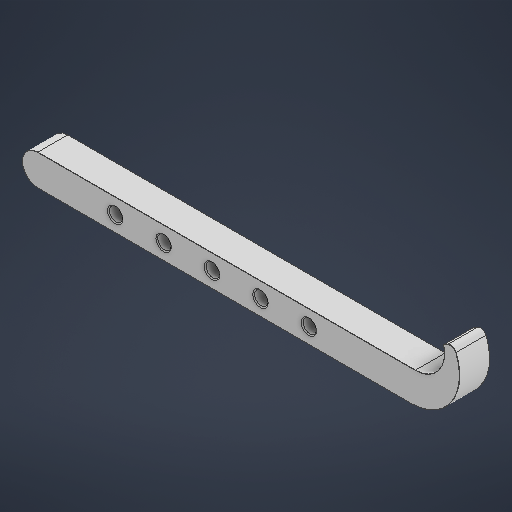
# Autodesk Inventor part: Part1
Saved by Autodesk Inventor 2025.4 (Build 294407000, 407)
## iProperties
Created: 2026-06-25
Part Number: Part1
Material: Generic
Document SubType Name: Modeling
Designer: VuQuan
Density: 1 g/cm^3
Appearance: Default
Author: VuQuan
Autodesk Inventor part; units mm, degrees
ref_plane "YZ Plane" through (0, 0, 0) normal (1, 0, 0) x (0, 1, 0)
ref_plane "XZ Plane" through (0, 0, 0) normal (0, 1, 0) x (-1, 0, 0)
ref_plane "XY Plane" through (0, 0, 0) normal (0, 0, 1) x (1, 0, 0)
sketch "Sketch1" plane through (0, 0, 0) normal (0, 0, 1) x (1, 0, 0)
  arc A0 (0, 8) -> (0, -8) centre (0, 0) ccw
  line L0 (0, 8) -> (195, 8)
  line L1 (0, -8) -> (192.8471, -8)
  arc A1 (195, 8) -> (209.5507, 26.6438) centre (195, 23) ccw
  arc A2 (192.8471, -8) -> (216, 26.4309) centre (192.8471, 17) ccw
  arc A3 (216, 26.4309) -> (211.7216, 27.8972) centre (213.2216, 25.2992) ccw
  line L2 (211.7216, 27.8972) -> (209.5507, 26.6438)
  circle A4 centre (40, 0) radius 3.5
  line L3 (0, 0) -> (40, 0) construction
  circle A5 centre (65, 0) radius 3.5
  circle A6 centre (90, 0) radius 3.5
  circle A7 centre (115, 0) radius 3.5
  circle A8 centre (140, 0) radius 3.5
  dimension "d1" = 8
  dimension "d2" = 195
  dimension "d3" = 15
  dimension "d5" = 25
  dimension "d6" = 3
  dimension "d7" = 21
  dimension "d8" = 30
  dimension "d9" = 7
  dimension "d10" = 40
  dimension "d13" = 25
  constraints: 9 centre point, 8 end point, 8 point on circle, 6 tangent, 4 horizontal, 1 coincident, 1 horizontal alignment, 1 point on line, 8 other
  measures "d1" radius of A0
  measures "d2" horizontal distance of A1.centre point (0, 0)
  measures "d3" radius of A1
  measures "d5" radius of A2
  measures "d6" radius of A3
  measures "d7" horizontal distance of A2.end A1.centre
  measures "d8" angle of L2 L1
  measures "d9" diameter of A4
  measures "d10" distance of point (0, 0) L3.end
  measures "d13" distance of L3.end A5.centre
extrude "Extrusion1" add sketch "Sketch1" along normal blind 15.6
fillet "Fillet1" radius 0.1 14 edges at (-8, 0, 15.6) (96.4235, -8, 15.6) (213.5928, 3.0496, 15.6) (214.1943, 28.1371, 15.6) (210.6362, 27.2705, 15.6) (206.8249, 13.7712, 15.6) (97.5, 8, 15.6) (-8, 0, 0) (96.4235, -8, 0) (213.5928, 3.0496, 0) (214.1943, 28.1371, 0) (210.6362, 27.2705, 0) (206.8249, 13.7712, 0) (97.5, 8, 0)
chamfer "Chamfer1" distance 0.5 angle 45 10 edges at (136.5, 0, 15.6) (111.5, 0, 15.6) (86.5, 0, 15.6) (61.5, 0, 15.6) (36.5, 0, 15.6) (136.5, 0, 0) (111.5, 0, 0) (86.5, 0, 0) (61.5, 0, 0) (36.5, 0, 0)
body "Solid1"
